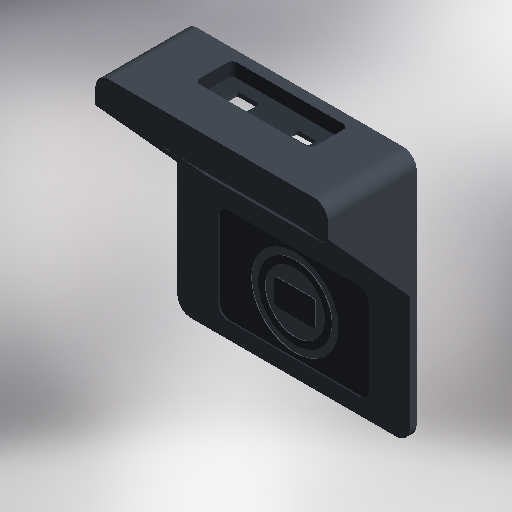
# Autodesk Inventor part: Enclosure_Top_Cover
Saved by Autodesk Inventor 2027.1 (Build 311270010, 270A)
## iProperties
Part Number: Enclosure_Top_Cover
Material: Generic
Document SubType Name: Modeling
Designer: austin
Appearance: Enclosure_Satin_Anthracite
Author: austin
Autodesk Inventor part; units mm, degrees
ref_plane "Work Plane1" through (0, 0, 18) normal (0, 0, 1) x (1, 0, 0)
sketch "Sketch1" plane through (0, 0, 18) normal (0, 0, 1) x (1, 0, 0)
  line L0 (-60, 0) -> (60, 0)
  arc A0 (60, 0) -> (68, 8) centre (60, 8) ccw
  line L1 (68, 8) -> (68, 137)
  arc A1 (68, 137) -> (60, 145) centre (60, 137) ccw
  line L2 (60, 145) -> (-60, 145)
  arc A2 (-60, 145) -> (-68, 137) centre (-60, 137) ccw
  line L3 (-68, 137) -> (-68, 8)
  arc A3 (-68, 8) -> (-60, 0) centre (-60, 8) ccw
  constraints: 8 end point, 8 point on circle, 4 centre point
extrude "Extrusion1" add sketch "Sketch1" along normal blind 57
sketch "Sketch2" plane through (0, 0, 0) normal (1, 0, 0) x (0, 1, 0)
  line L0 (0, 22) -> (0, 85)
  line L1 (0, 85) -> (150, 85)
  line L2 (150, 85) -> (150, 70)
  line L3 (150, 70) -> (145, 70)
  line L4 (145, 70) -> (128, 70)
  line L5 (128, 70) -> (75, 22)
  line L6 (75, 22) -> (0, 22)
  constraints: 14 end point
extrude "Extrusion2" cut sketch "Sketch2" along normal mid plane 150
sketch "Sketch3" plane through (0, 0, 0) normal (1, 0, 0) x (0, 1, 0)
  line L0 (2.5, 18) -> (2.5, 19.5)
  line L1 (2.5, 19.5) -> (75, 19.5)
  line L2 (75, 19.5) -> (126, 64.5)
  line L3 (126, 64.5) -> (142.5, 67.5)
  line L4 (142.5, 67.5) -> (142.5, 18)
  line L5 (142.5, 18) -> (2.5, 18)
  constraints: 12 end point
extrude "Extrusion3" cut sketch "Sketch3" along normal mid plane 131
ref_plane "Work Plane2" through (-68, 75, 22) normal (0, 0, 1) x (1, 0, 0)
ref_plane "Work Plane3" through (-68, 128, 70) normal (0, -0.6712794, 0.7412044) x (1, 0, 0)
sketch "Sketch4" plane through (-68, 75, 22) normal (0, 0, 1) x (1, 0, 0)
  line L0 (30, -65.5) -> (106, -65.5)
  arc A0 (106, -65.5) -> (112, -59.5) centre (106, -59.5) ccw
  line L1 (112, -59.5) -> (112, -15.5)
  arc A1 (112, -15.5) -> (106, -9.5) centre (106, -15.5) ccw
  line L2 (106, -9.5) -> (30, -9.5)
  arc A2 (30, -9.5) -> (24, -15.5) centre (30, -15.5) ccw
  line L3 (24, -15.5) -> (24, -59.5)
  arc A3 (24, -59.5) -> (30, -65.5) centre (30, -59.5) ccw
  constraints: 8 end point, 8 point on circle, 4 centre point
extrude "Extrusion4" cut sketch "Sketch4" against normal blind 0.8
sketch "Sketch5" plane through (-68, 75, 22) normal (0, 0, 1) x (1, 0, 0)
  line L0 (57.8, -45) -> (78.2, -45)
  arc A0 (78.2, -45) -> (80, -43.2) centre (78.2, -43.2) ccw
  line L1 (80, -43.2) -> (80, -31.8)
  arc A1 (80, -31.8) -> (78.2, -30) centre (78.2, -31.8) ccw
  line L2 (78.2, -30) -> (57.8, -30)
  arc A2 (57.8, -30) -> (56, -31.8) centre (57.8, -31.8) ccw
  line L3 (56, -31.8) -> (56, -43.2)
  arc A3 (56, -43.2) -> (57.8, -45) centre (57.8, -43.2) ccw
  arc A4 (54.8936, -28.3228) -> (54.8936, -46.6772) centre (68, -37.5) ccw
  line L4 (54.8936, -46.6772) -> (53.6648, -47.5376)
  arc A5 (53.6648, -47.5376) -> (53.6648, -27.4624) centre (68, -37.5) ccw
  line L5 (53.6648, -27.4624) -> (54.8936, -28.3228)
  arc A6 (51.039, -26.9016) -> (51.039, -48.0984) centre (68, -37.5) ccw
  line L6 (51.039, -48.0984) -> (49.767, -48.8933)
  arc A7 (49.767, -48.8933) -> (49.767, -26.1067) centre (68, -37.5) ccw
  line L7 (49.767, -26.1067) -> (51.039, -26.9016)
  arc A8 (47.2154, -25.5) -> (47.2154, -49.5) centre (68, -37.5) ccw
  line L8 (47.2154, -49.5) -> (45.9164, -50.25)
  arc A9 (45.9164, -50.25) -> (45.9164, -24.75) centre (68, -37.5) ccw
  line L9 (45.9164, -24.75) -> (47.2154, -25.5)
  arc A10 (81.1064, -46.6772) -> (81.1064, -28.3228) centre (68, -37.5) ccw
  line L10 (81.1064, -28.3228) -> (82.3352, -27.4624)
  arc A11 (82.3352, -27.4624) -> (82.3352, -47.5376) centre (68, -37.5) ccw
  line L11 (82.3352, -47.5376) -> (81.1064, -46.6772)
  arc A12 (84.961, -48.0984) -> (84.961, -26.9016) centre (68, -37.5) ccw
  line L12 (84.961, -26.9016) -> (86.233, -26.1067)
  arc A13 (86.233, -26.1067) -> (86.233, -48.8933) centre (68, -37.5) ccw
  line L13 (86.233, -48.8933) -> (84.961, -48.0984)
  arc A14 (88.7846, -49.5) -> (88.7846, -25.5) centre (68, -37.5) ccw
  line L14 (88.7846, -25.5) -> (90.0836, -24.75)
  arc A15 (90.0836, -24.75) -> (90.0836, -50.25) centre (68, -37.5) ccw
  line L15 (90.0836, -50.25) -> (88.7846, -49.5)
  constraints: 32 end point, 32 point on circle, 16 centre point
extrude "Extrusion5" cut sketch "Sketch5" against normal blind 1.2
sketch "Sketch6" plane through (-68, 128, 70) normal (0, -0.6712794, 0.7412044) x (1, 0, 0)
  line L0 (34.5, -46.7526) -> (101.5, -46.7526)
  arc A0 (101.5, -46.7526) -> (103, -45.2526) centre (101.5, -45.2526) ccw
  line L1 (103, -45.2526) -> (103, -26.2526)
  arc A1 (103, -26.2526) -> (101.5, -24.7526) centre (101.5, -26.2526) ccw
  line L2 (101.5, -24.7526) -> (34.5, -24.7526)
  arc A2 (34.5, -24.7526) -> (33, -26.2526) centre (34.5, -26.2526) ccw
  line L3 (33, -26.2526) -> (33, -45.2526)
  arc A3 (33, -45.2526) -> (34.5, -46.7526) centre (34.5, -45.2526) ccw
  constraints: 8 end point, 8 point on circle, 4 centre point
extrude "Extrusion6" cut sketch "Sketch6" against normal blind 25
sketch "Sketch7" plane through (-68, 128, 70) normal (0, -0.6712794, 0.7412044) x (1, 0, 0)
  circle A0 centre (26, -23.7526) radius 1.6
  constraints: 1 centre point
extrude "Extrusion7" cut sketch "Sketch7" against normal blind 25
ref_plane "Work Plane4" through (0, 145, 0) normal (0, 1, 0) x (-1, 0, 0)
sketch "Sketch8" plane through (0, 145, 0) normal (0, 1, 0) x (-1, 0, 0)
  line L0 (-32.5, 21.5) -> (32.5, 21.5)
  arc A0 (32.5, 21.5) -> (36.5, 25.5) centre (32.5, 25.5) ccw
  line L1 (36.5, 25.5) -> (36.5, 44.5)
  arc A1 (36.5, 44.5) -> (32.5, 48.5) centre (32.5, 44.5) ccw
  line L2 (32.5, 48.5) -> (-32.5, 48.5)
  arc A2 (-32.5, 48.5) -> (-36.5, 44.5) centre (-32.5, 44.5) ccw
  line L3 (-36.5, 44.5) -> (-36.5, 25.5)
  arc A3 (-36.5, 25.5) -> (-32.5, 21.5) centre (-32.5, 25.5) ccw
  constraints: 8 end point, 8 point on circle, 4 centre point
extrude "Extrusion8" add sketch "Sketch8" against normal blind 10.5
sketch "Sketch9" plane through (0, 145, 0) normal (0, 1, 0) x (-1, 0, 0)
  line L0 (-31, 24) -> (31, 24)
  arc A0 (31, 24) -> (34, 27) centre (31, 27) ccw
  line L1 (34, 27) -> (34, 43)
  arc A1 (34, 43) -> (31, 46) centre (31, 43) ccw
  line L2 (31, 46) -> (-31, 46)
  arc A2 (-31, 46) -> (-34, 43) centre (-31, 43) ccw
  line L3 (-34, 43) -> (-34, 27)
  arc A3 (-34, 27) -> (-31, 24) centre (-31, 27) ccw
  constraints: 8 end point, 8 point on circle, 4 centre point
extrude "Extrusion9" cut sketch "Sketch9" against normal blind 8
ref_plane "Work Plane5" through (0, 137, 0) normal (0, 1, 0) x (-1, 0, 0)
sketch "Sketch10" plane through (0, 137, 0) normal (0, 1, 0) x (-1, 0, 0)
  line L0 (12.3, 30.5) -> (23.7, 30.5)
  arc A0 (23.7, 30.5) -> (24.5, 31.3) centre (23.7, 31.3) ccw
  line L1 (24.5, 31.3) -> (24.5, 38.7)
  arc A1 (24.5, 38.7) -> (23.7, 39.5) centre (23.7, 38.7) ccw
  line L2 (23.7, 39.5) -> (12.3, 39.5)
  arc A2 (12.3, 39.5) -> (11.5, 38.7) centre (12.3, 38.7) ccw
  line L3 (11.5, 38.7) -> (11.5, 31.3)
  arc A3 (11.5, 31.3) -> (12.3, 30.5) centre (12.3, 31.3) ccw
  line L4 (-22, 32.5) -> (-14, 32.5)
  arc A4 (-14, 32.5) -> (-12, 34.5) centre (-14, 34.5) ccw
  line L5 (-12, 34.5) -> (-12, 35.5)
  arc A5 (-12, 35.5) -> (-14, 37.5) centre (-14, 35.5) ccw
  line L6 (-14, 37.5) -> (-22, 37.5)
  arc A6 (-22, 37.5) -> (-24, 35.5) centre (-22, 35.5) ccw
  line L7 (-24, 35.5) -> (-24, 34.5)
  arc A7 (-24, 34.5) -> (-22, 32.5) centre (-22, 34.5) ccw
  constraints: 16 end point, 16 point on circle, 8 centre point
extrude "Extrusion10" cut sketch "Sketch10" against normal blind 3.5
sketch "Sketch11" plane through (0, 0, 18) normal (0, 0, 1) x (1, 0, 0)
  circle A0 centre (-59, 11) radius 4
  circle A1 centre (59, 11) radius 4
  constraints: 2 centre point
extrude "Extrusion11" add sketch "Sketch11" along normal blind 4
sketch "Sketch12" plane through (0, 0, 18) normal (0, 0, 1) x (1, 0, 0)
  line L0 (57, 8) -> (66.5, 8)
  line L1 (66.5, 8) -> (66.5, 14)
  line L2 (66.5, 14) -> (57, 14)
  line L3 (57, 14) -> (57, 8)
  line L4 (56, 1.5) -> (56, 12)
  line L5 (56, 12) -> (62, 12)
  line L6 (62, 12) -> (62, 1.5)
  line L7 (62, 1.5) -> (56, 1.5)
  line L8 (-66.5, 8) -> (-57, 8)
  line L9 (-57, 8) -> (-57, 14)
  line L10 (-57, 14) -> (-66.5, 14)
  line L11 (-66.5, 14) -> (-66.5, 8)
  line L12 (-62, 1.5) -> (-62, 12)
  line L13 (-62, 12) -> (-56, 12)
  line L14 (-56, 12) -> (-56, 1.5)
  line L15 (-56, 1.5) -> (-62, 1.5)
  constraints: 32 end point
extrude "Extrusion12" add sketch "Sketch12" along normal blind 4
sketch "Sketch13" plane through (0, 0, 18) normal (0, 0, 1) x (1, 0, 0)
  circle A0 centre (-59, 11) radius 1.4
  circle A1 centre (59, 11) radius 1.4
  constraints: 2 centre point
extrude "Extrusion13" cut sketch "Sketch13" along normal blind 3.2
sketch "Sketch14" plane through (0, 0, 18) normal (0, 0, 1) x (1, 0, 0)
  circle A0 centre (-59, 134) radius 4.5
  circle A1 centre (59, 134) radius 4.5
  constraints: 2 centre point
extrude "Extrusion14" add sketch "Sketch14" along normal blind 48
sketch "Sketch15" plane through (0, 0, 18) normal (0, 0, 1) x (1, 0, 0)
  line L0 (57, 131) -> (66.5, 131)
  line L1 (66.5, 131) -> (66.5, 137)
  line L2 (66.5, 137) -> (57, 137)
  line L3 (57, 137) -> (57, 131)
  line L4 (56, 133) -> (56, 143.5)
  line L5 (56, 143.5) -> (62, 143.5)
  line L6 (62, 143.5) -> (62, 133)
  line L7 (62, 133) -> (56, 133)
  line L8 (-66.5, 131) -> (-57, 131)
  line L9 (-57, 131) -> (-57, 137)
  line L10 (-57, 137) -> (-66.5, 137)
  line L11 (-66.5, 137) -> (-66.5, 131)
  line L12 (-62, 133) -> (-62, 143.5)
  line L13 (-62, 143.5) -> (-56, 143.5)
  line L14 (-56, 143.5) -> (-56, 133)
  line L15 (-56, 133) -> (-62, 133)
  constraints: 32 end point
extrude "Extrusion15" add sketch "Sketch15" along normal blind 48
sketch "Sketch16" plane through (0, 0, 18) normal (0, 0, 1) x (1, 0, 0)
  circle A0 centre (-59, 134) radius 1.4
  circle A1 centre (59, 134) radius 1.4
  constraints: 2 centre point
extrude "Extrusion16" cut sketch "Sketch16" along normal blind 10
body "Solid1"
